Autodesk Fusion 360 part; units mm, degrees
(part 15 of 18)
  line L11676 (45.6204, -120.427) -> (45.1214, -120.123)
  line L11677 (160.483, -103.604) -> (159.889, -103.597)
  line L11678 (46.138, -120.698) -> (45.6204, -120.427)
  line L11679 (46.672, -120.935) -> (46.138, -120.698)
  line L11680 (87.7561, -119.027) -> (87.3513, -118.606)
  line L11681 (41.1245, -112.331) -> (41.1297, -112.925)
  line L11682 (41.1297, -112.925) -> (41.1742, -113.517)
  line L11683 (90.8336, -104.101) -> (91.3856, -103.909)
  line L11684 (59.1268, -112.55) -> (59.1251, -112.724)
  line L11685 (59.1079, -111.966) -> (59.1268, -112.55)
  line L11686 (54.0441, -120.684) -> (53.5109, -120.923)
  line L11687 (54.5607, -120.411) -> (54.0441, -120.684)
  line L11688 (55.0587, -120.105) -> (54.5607, -120.411)
  line L11689 (89.1214, -120.123) -> (88.643, -119.787)
  line L11690 (92.1233, -103.811) -> (91.5484, -103.959)
  line L11691 (55.2028, -105.092) -> (55.6734, -105.438)
  line L11692 (93.8893, -103.597) -> (93.2963, -103.629)
  line L11693 (54.7108, -104.776) -> (55.2028, -105.092)
  line L11694 (59.0274, -113.888) -> (58.9224, -114.462)
  line L11695 (59.0951, -113.307) -> (59.0274, -113.888)
  line L11696 (59.1251, -112.724) -> (59.0951, -113.307)
  line L11697 (90.672, -120.935) -> (90.138, -120.698)
  line L11698 (99.4411, -105.379) -> (98.954, -105.04)
  line L11699 (99.9045, -105.751) -> (99.4411, -105.379)
  line L11700 (46.8336, -104.101) -> (47.3856, -103.909)
  line L11701 (46.2951, -104.328) -> (46.8336, -104.101)
  line L11702 (56.5428, -106.218) -> (56.9379, -106.649)
  line L11703 (55.6734, -105.438) -> (56.1207, -105.814)
  line L11704 (92.35, -121.434) -> (91.7803, -121.304)
  line L11705 (56.1207, -105.814) -> (56.5428, -106.218)
  line L11706 (90.9847, -104.146) -> (90.4345, -104.369)
  line L11707 (92.7068, -103.7) -> (92.1233, -103.811)
  line L11708 (41.2769, -110.437) -> (41.4315, -109.874)
  line L11709 (41.1589, -111.01) -> (41.2769, -110.437)
  line L11710 (48.5208, -103.635) -> (49.0994, -103.553)
  line L11711 (47.9488, -103.754) -> (48.5208, -103.635)
  line L11712 (47.3856, -103.909) -> (47.9488, -103.754)
  line L11713 (93.2963, -103.629) -> (92.7068, -103.7)
  line L11714 (90.4345, -104.369) -> (89.9003, -104.629)
  line L11715 (94.0926, -121.6) -> (93.5085, -121.582)
  line L11716 (153.549, -106.42) -> (153.157, -106.866)
  line L11717 (41.8482, -108.783) -> (42.1085, -108.26)
  line L11718 (41.6223, -109.322) -> (41.8482, -108.783)
  line L11719 (153.97, -106.001) -> (153.549, -106.42)
  line L11720 (41.4315, -109.874) -> (41.6223, -109.322)
  line L11721 (95.8346, -121.428) -> (95.2581, -121.523)
  line L11722 (89.9003, -104.629) -> (89.3845, -104.923)
  line L11723 (88.417, -105.61) -> (87.9695, -106.001)
  line L11724 (58.5935, -115.317) -> (58.7582, -114.747)
  line L11725 (57.8006, -108.018) -> (57.4833, -107.517)
  line L11726 (58.084, -108.54) -> (57.8006, -108.018)
  line L11727 (58.3914, -115.876) -> (58.5935, -115.317)
  line L11728 (58.3321, -109.08) -> (58.084, -108.54)
  line L11729 (85.1742, -113.517) -> (85.2578, -114.105)
  line L11730 (98.4456, -104.733) -> (97.9179, -104.461)
  line L11731 (54.5813, -120.29) -> (55.0844, -119.974)
  line L11732 (58.9725, -113.579) -> (59.0211, -112.987)
  line L11733 (55.0844, -119.974) -> (55.5654, -119.626)
  line L11734 (58.8847, -114.167) -> (58.9725, -113.579)
  line L11735 (58.7582, -114.747) -> (58.8847, -114.167)
  line L11736 (85.0332, -112.331) -> (85.0347, -112.171)
  line L11737 (155.9, -104.629) -> (155.385, -104.923)
  line L11738 (85.2769, -110.437) -> (85.4315, -109.874)
  line L11739 (100.856, -118.401) -> (101.229, -117.939)
  line L11740 (87.2572, -118.354) -> (87.6569, -118.793)
  line L11741 (102.758, -114.747) -> (102.885, -114.167)
  line L11742 (92.9269, -121.527) -> (92.35, -121.434)
  line L11743 (103.032, -112.55) -> (103.012, -111.957)
  line L11744 (49.4521, -121.483) -> (50.0455, -121.505)
  line L11745 (56.453, -118.838) -> (56.8557, -118.401)
  line L11746 (56.0223, -119.247) -> (56.453, -118.838)
  line L11747 (48.8615, -121.422) -> (49.4521, -121.483)
  line L11748 (55.5654, -119.626) -> (56.0223, -119.247)
  line L11749 (85.0612, -113.339) -> (85.0291, -112.755)
  line L11750 (103.021, -112.987) -> (103.032, -112.55)
  line L11751 (102.972, -113.579) -> (103.021, -112.987)
  line L11752 (43.6569, -118.793) -> (44.0847, -119.205)
  line L11753 (51.2302, -121.43) -> (51.8162, -121.334)
  line L11754 (44.0847, -119.205) -> (44.539, -119.587)
  line L11755 (50.6391, -121.487) -> (51.2302, -121.43)
  line L11756 (50.0455, -121.505) -> (50.6391, -121.487)
  line L11757 (85.2379, -114.493) -> (85.1309, -113.919)
  line L11758 (101.133, -107.037) -> (100.753, -106.581)
  line L11759 (41.2578, -114.105) -> (41.3803, -114.686)
  line L11760 (41.1742, -113.517) -> (41.2578, -114.105)
  line L11761 (101.483, -107.517) -> (101.133, -107.037)
  line L11762 (45.0175, -119.939) -> (45.5183, -120.258)
  line L11763 (44.539, -119.587) -> (45.0175, -119.939)
  line L11764 (85.5618, -115.616) -> (85.3817, -115.06)
  line L11765 (177.268, -104.884) -> (177.772, -104.589)
  line L11766 (177.772, -104.589) -> (178.295, -104.328)
  line L11767 (41.7774, -116.159) -> (41.5618, -115.616)
  line L11768 (159.889, -103.597) -> (159.296, -103.629)
  line L11769 (42.0276, -116.687) -> (41.7774, -116.159)
  line L11770 (167.483, -107.517) -> (167.133, -107.037)
  line L11771 (41.7392, -115.817) -> (41.9741, -116.363)
  line L11772 (41.541, -115.258) -> (41.7392, -115.817)
  line L11773 (86.0276, -116.687) -> (85.7774, -116.159)
  line L11774 (178.295, -104.328) -> (178.834, -104.101)
  line L11775 (41.3803, -114.686) -> (41.541, -115.258)
  line L11776 (95.075, -103.651) -> (94.483, -103.604)
  line L11777 (47.2202, -121.137) -> (46.672, -120.935)
  line L11778 (47.7803, -121.304) -> (47.2202, -121.137)
  line L11779 (41.2379, -114.493) -> (41.1309, -113.919)
  line L11780 (85.3443, -110.566) -> (85.2321, -111.149)
  line L11781 (47.6987, -121.183) -> (48.2761, -121.322)
  line L11782 (57.1334, -107.037) -> (56.7525, -106.581)
  line L11783 (47.1318, -121.007) -> (47.6987, -121.183)
  line L11784 (54.0585, -120.571) -> (54.5813, -120.29)
  line L11785 (51.8162, -121.334) -> (52.3945, -121.2)
  line L11786 (59.0121, -111.957) -> (58.9531, -111.366)
  line L11787 (51.075, -103.651) -> (50.483, -103.604)
  line L11788 (57.8785, -116.946) -> (58.1527, -116.419)
  line L11789 (186.199, -104.494) -> (186.711, -104.776)
  line L11790 (53.5182, -120.817) -> (54.0585, -120.571)
  line L11791 (96.9634, -121.127) -> (96.4039, -121.296)
  line L11792 (102.659, -109.678) -> (102.827, -110.238)
  line L11793 (52.9627, -121.027) -> (53.5182, -120.817)
  line L11794 (161.663, -103.737) -> (161.075, -103.651)
  line L11795 (162.243, -103.861) -> (161.663, -103.737)
  line L11796 (152.795, -107.337) -> (152.466, -107.831)
  line L11797 (173.159, -111.01) -> (173.277, -110.437)
  line L11798 (152.466, -107.831) -> (152.17, -108.346)
  line L11799 (153.157, -106.866) -> (152.795, -107.337)
  line L11800 (151.232, -111.149) -> (151.159, -111.738)
  line L11801 (42.402, -107.754) -> (42.7274, -107.269)
  line L11802 (158.123, -103.811) -> (157.548, -103.959)
  line L11803 (49.5085, -121.582) -> (48.9269, -121.527)
  line L11804 (58.9224, -114.462) -> (58.7806, -115.029)
  line L11805 (45.3845, -104.923) -> (44.8893, -105.251)
  line L11806 (168.972, -113.579) -> (169.021, -112.987)
  line L11807 (58.7806, -115.029) -> (58.6024, -115.586)
  line L11808 (48.2761, -121.322) -> (48.8615, -121.422)
  line L11809 (100.823, -118.582) -> (100.42, -119.005)
  line L11810 (53.671, -104.244) -> (54.1995, -104.494)
  line L11811 (157.548, -103.959) -> (156.985, -104.146)
  line L11812 (175.469, -106.366) -> (175.882, -105.953)
  line L11813 (58.8266, -110.238) -> (58.9575, -110.808)
  line L11814 (167.57, -117.453) -> (167.879, -116.946)
  line L11815 (48.9269, -121.527) -> (48.35, -121.434)
  line L11816 (88.7829, -105.21) -> (89.2676, -104.884)
  line L11817 (168.084, -108.54) -> (167.801, -108.018)
  line L11818 (99.0587, -120.105) -> (98.5607, -120.411)
  line L11819 (57.5441, -117.663) -> (57.1986, -118.134)
  line L11820 (165.441, -105.379) -> (164.954, -105.04)
  line L11821 (43.2572, -118.354) -> (43.6569, -118.793)
  line L11822 (102.781, -115.029) -> (102.602, -115.586)
  line L11823 (98.5607, -120.411) -> (98.0441, -120.684)
  line L11824 (90.138, -120.698) -> (89.6204, -120.427)
  line L11825 (99.5654, -119.626) -> (100.022, -119.247)
  line L11826 (87.5489, -106.42) -> (87.157, -106.866)
  line L11827 (85.2578, -114.105) -> (85.3803, -114.686)
  line L11828 (58.8551, -110.78) -> (58.7185, -110.202)
  line L11829 (88.0847, -119.205) -> (88.539, -119.587)
  line L11830 (58.9575, -110.808) -> (59.0514, -111.384)
  line L11831 (154.889, -105.251) -> (154.417, -105.61)
  line L11832 (42.17, -108.346) -> (41.9088, -108.879)
  line L11833 (165.904, -105.751) -> (165.441, -105.379)
  line L11834 (90.0392, -120.543) -> (90.5778, -120.793)
  line L11835 (182.85, -103.533) -> (183.43, -103.602)
  line L11836 (58.1404, -116.659) -> (57.8585, -117.17)
  line L11837 (57.1986, -118.134) -> (56.8234, -118.582)
  line L11838 (50.8498, -103.533) -> (51.4301, -103.602)
  line L11839 (43.8816, -105.953) -> (44.3203, -105.567)
  line L11840 (102.456, -109.131) -> (102.659, -109.678)
  line L11841 (96.9627, -121.027) -> (97.5182, -120.817)
  line L11842 (86.3113, -117.198) -> (86.0276, -116.687)
  line L11843 (167.133, -107.037) -> (166.753, -106.581)
  line L11844 (168.953, -111.366) -> (168.855, -110.78)
  line L11845 (88.3203, -105.567) -> (88.7829, -105.21)
  line L11846 (179.949, -103.754) -> (180.521, -103.635)
  line L11847 (103.108, -111.966) -> (103.127, -112.55)
  line L11848 (46.0392, -120.543) -> (46.5778, -120.793)
  line L11849 (50.2663, -103.502) -> (50.8498, -103.533)
  line L11850 (168.885, -114.167) -> (168.972, -113.579)
  line L11851 (164.954, -105.04) -> (164.446, -104.733)
  line L11852 (101.199, -118.134) -> (100.823, -118.582)
  line L11853 (97.3734, -104.224) -> (96.8143, -104.024)
  line L11854 (102.602, -115.586) -> (102.389, -116.13)
  line L11855 (168.719, -110.202) -> (168.544, -109.635)
  line L11856 (43.0836, -106.806) -> (43.4688, -106.366)
  line L11857 (101.879, -116.946) -> (102.153, -116.419)
  line L11858 (151.683, -109.429) -> (151.495, -109.992)
  line L11859 (58.2178, -108.597) -> (58.4559, -109.131)
  line L11860 (85.4315, -109.874) -> (85.6222, -109.322)
  line L11861 (183.43, -103.602) -> (184.005, -103.708)
  line L11862 (85.6222, -109.322) -> (85.8482, -108.783)
  line L11863 (166.342, -106.152) -> (165.904, -105.751)
  line L11864 (92.5208, -103.635) -> (93.0994, -103.553)
  line L11865 (179.386, -103.909) -> (179.949, -103.754)
  line L11866 (91.2202, -121.137) -> (90.672, -120.935)
  line L11867 (94.6766, -121.58) -> (94.0926, -121.6)
  line L11868 (96.8143, -104.024) -> (96.2432, -103.861)
  line L11869 (102.855, -110.78) -> (102.719, -110.202)
  line L11870 (168.594, -115.317) -> (168.758, -114.747)
  line L11871 (102.544, -109.635) -> (102.332, -109.08)
  line L11872 (168.758, -114.747) -> (168.885, -114.167)
  line L11873 (102.719, -110.202) -> (102.544, -109.635)
  line L11874 (99.9903, -119.401) -> (99.5358, -119.768)
  line L11875 (156.434, -104.369) -> (155.9, -104.629)
  line L11876 (58.9531, -111.366) -> (58.8551, -110.78)
  line L11877 (184.571, -103.851) -> (185.128, -104.03)
  line L11878 (91.7803, -121.304) -> (91.2202, -121.137)
  line L11879 (44.7829, -105.21) -> (45.2676, -104.884)
  line L11880 (86.9746, -118.159) -> (86.6274, -117.689)
  line L11881 (41.0612, -113.339) -> (41.0291, -112.755)
  line L11882 (41.0291, -112.755) -> (41.0332, -112.331)
  line L11883 (166.453, -118.838) -> (166.856, -118.401)
  line L11884 (46.9847, -104.146) -> (46.4345, -104.369)
  line L11885 (42.9746, -118.159) -> (42.6274, -117.689)
  line L11886 (44.8893, -105.251) -> (44.417, -105.61)
  line L11887 (167.229, -117.939) -> (167.57, -117.453)
  line L11888 (88.643, -119.787) -> (88.1873, -119.421)
  line L11889 (86.5495, -117.401) -> (86.8876, -117.889)
  line L11890 (41.078, -111.588) -> (41.1589, -111.01)
  line L11891 (45.9003, -104.629) -> (45.3845, -104.923)
  line L11892 (162.814, -104.024) -> (162.243, -103.861)
  line L11893 (173.848, -108.783) -> (174.108, -108.26)
  line L11894 (57.9457, -108.08) -> (58.2178, -108.597)
  line L11895 (50.0926, -121.6) -> (49.5085, -121.582)
  line L11896 (42.466, -107.831) -> (42.17, -108.346)
  line L11897 (88.1873, -119.421) -> (87.7561, -119.027)
  line L11898 (93.682, -103.509) -> (94.2663, -103.502)
  line L11899 (94.2663, -103.502) -> (94.8498, -103.533)
  line L11900 (186.711, -104.776) -> (187.203, -105.092)
  line L11901 (100.121, -105.814) -> (100.543, -106.218)
  line L11902 (51.4301, -103.602) -> (52.0047, -103.708)
  line L11903 (100.42, -119.005) -> (99.9903, -119.401)
  line L11904 (59.0514, -111.384) -> (59.1079, -111.966)
  line L11905 (96.4039, -121.296) -> (95.8346, -121.428)
  line L11906 (156.985, -104.146) -> (156.434, -104.369)
  line L11907 (86.17, -108.346) -> (85.9088, -108.879)
  line L11908 (46.5778, -120.793) -> (47.1318, -121.007)
  line L11909 (89.2676, -104.884) -> (89.7724, -104.589)
  line L11910 (154.417, -105.61) -> (153.97, -106.001)
  line L11911 (48.35, -121.434) -> (47.7803, -121.304)
  line L11912 (85.2321, -111.149) -> (85.1587, -111.738)
  line L11913 (52.9634, -121.127) -> (52.4039, -121.296)
  line L11914 (98.0441, -120.684) -> (97.5109, -120.923)
  line L11915 (85.1297, -112.925) -> (85.1742, -113.517)
  line L11916 (44.3203, -105.567) -> (44.7829, -105.21)
  line L11917 (42.5495, -117.401) -> (42.8876, -117.889)
  line L11918 (87.4688, -106.366) -> (87.8816, -105.953)
  line L11919 (87.8816, -105.953) -> (88.3203, -105.567)
  line L11920 (165.565, -119.626) -> (166.022, -119.247)
  line L11921 (163.373, -104.224) -> (162.814, -104.024)
  line L11922 (173.277, -110.437) -> (173.432, -109.874)
  line L11923 (85.078, -111.588) -> (85.1589, -111.01)
  line L11924 (52.4039, -121.296) -> (51.8346, -121.428)
  line L11925 (86.7955, -107.337) -> (86.466, -107.831)
  line L11926 (57.8585, -117.17) -> (57.5441, -117.663)
  line L11927 (87.157, -106.866) -> (86.7955, -107.337)
  line L11928 (41.3817, -115.06) -> (41.2379, -114.493)
  line L11929 (146.389, -116.13) -> (146.14, -116.659)
  line L11930 (130.466, -107.831) -> (130.17, -108.346)
  line L11931 (123.133, -107.037) -> (122.753, -106.581)
  line L11932 (108.17, -108.346) -> (107.909, -108.879)
  line L11933 (157.949, -103.754) -> (158.521, -103.635)
  line L11934 (145.544, -117.663) -> (145.199, -118.134)
  line L11935 (143.203, -105.092) -> (143.673, -105.438)
  line L11936 (110.417, -105.61) -> (109.97, -106.001)
  line L11937 (138.046, -121.505) -> (138.639, -121.487)
  line L11938 (137.452, -121.483) -> (138.046, -121.505)
  line L11939 (107.159, -111.738) -> (107.124, -112.331)
  line L11940 (133.772, -104.589) -> (134.295, -104.328)
  line L11941 (164.561, -120.411) -> (164.044, -120.684)
  line L11942 (156.672, -120.935) -> (156.138, -120.698)
  line L11943 (155.018, -119.939) -> (155.518, -120.258)
  line L11944 (124.972, -113.579) -> (125.021, -112.987)
  line L11945 (166.938, -106.649) -> (167.304, -107.104)
  line L11946 (151.38, -114.686) -> (151.541, -115.258)
  line L11947 (159.099, -103.553) -> (159.682, -103.509)
  line L11948 (134.039, -120.543) -> (134.578, -120.793)
  line L11949 (109.97, -106.001) -> (109.549, -106.42)
  line L11950 (131.549, -106.42) -> (131.157, -106.866)
  line L11951 (121.565, -119.626) -> (122.022, -119.247)
  line L11952 (117.23, -121.43) -> (117.816, -121.334)
  line L11953 (112.985, -104.146) -> (112.434, -104.369)
  line L11954 (142.199, -104.494) -> (142.711, -104.776)
  line L11955 (146.659, -109.678) -> (146.827, -110.238)
  line L11956 (159.509, -121.582) -> (158.927, -121.527)
  line L11957 (140.963, -121.127) -> (140.404, -121.296)
  line L11958 (138.677, -121.58) -> (138.093, -121.6)
  line L11959 (151.258, -114.105) -> (151.38, -114.686)
  line L11960 (142.561, -120.411) -> (142.044, -120.684)
  line L11961 (139.075, -103.651) -> (138.483, -103.604)
  line L11962 (141.511, -120.923) -> (140.963, -121.127)
  line L11963 (125.125, -112.724) -> (125.095, -113.307)
  line L11964 (123.483, -107.517) -> (123.133, -107.037)
  line L11965 (163.511, -120.923) -> (162.963, -121.127)
  line L11966 (129.683, -109.429) -> (129.495, -109.992)
  line L11967 (130.245, -116.891) -> (130.55, -117.401)
  line L11968 (145.858, -117.17) -> (145.544, -117.663)
  line L11969 (107.124, -112.331) -> (107.13, -112.925)
  line L11970 (146.391, -115.876) -> (146.594, -115.317)
  line L11971 (141.671, -104.244) -> (142.199, -104.494)
  line L11972 (165.673, -105.438) -> (166.121, -105.814)
  line L11973 (161.258, -121.523) -> (160.677, -121.58)
  line L11974 (132.32, -105.567) -> (132.783, -105.21)
  line L11975 (144.856, -118.401) -> (145.229, -117.939)
  line L11976 (129.739, -115.817) -> (129.974, -116.363)
  line L11977 (146.218, -108.597) -> (146.456, -109.131)
  line L11978 (145.879, -116.946) -> (146.153, -116.419)
  line L11979 (146.456, -109.131) -> (146.659, -109.678)
  line L11980 (108.466, -107.831) -> (108.17, -108.346)
  line L11981 (142.711, -104.776) -> (143.203, -105.092)
  line L11982 (152.727, -107.269) -> (153.084, -106.806)
  line L11983 (115.296, -103.629) -> (114.707, -103.7)
  line L11984 (146.957, -110.808) -> (147.051, -111.384)
  line L11985 (152.108, -108.26) -> (152.402, -107.754)
  line L11986 (142.581, -120.29) -> (143.084, -119.974)
  line L11987 (117.663, -103.737) -> (117.075, -103.651)
  line L11988 (146.602, -115.586) -> (146.389, -116.13)
  line L11989 (135.78, -121.304) -> (135.22, -121.137)
  line L11990 (157.132, -121.007) -> (157.699, -121.183)
  line L11991 (151.061, -113.339) -> (151.029, -112.755)
  line L11992 (136.35, -121.434) -> (135.78, -121.304)
  line L11993 (143.084, -119.974) -> (143.565, -119.626)
  line L11994 (151.277, -110.437) -> (151.432, -109.874)
  line L11995 (129.777, -116.159) -> (129.562, -115.616)
  line L11996 (147.108, -111.966) -> (147.127, -112.55)
  line L11997 (139.816, -121.334) -> (140.395, -121.2)
  line L11998 (158.521, -103.635) -> (159.099, -103.553)
  line L11999 (153.257, -118.354) -> (153.657, -118.793)
  line L12000 (146.084, -108.54) -> (145.801, -108.018)
  line L12001 (143.565, -119.626) -> (144.022, -119.247)
  line L12002 (109.157, -106.866) -> (108.795, -107.337)
  line L12003 (146.827, -110.238) -> (146.957, -110.808)
  line L12004 (141.128, -104.03) -> (141.671, -104.244)
  line L12005 (135.22, -121.137) -> (134.672, -120.935)
  line L12006 (169.027, -113.888) -> (168.922, -114.462)
  line L12007 (168.957, -110.808) -> (169.051, -111.384)
  line L12008 (124.544, -109.635) -> (124.332, -109.08)
  line L12009 (124.758, -114.747) -> (124.885, -114.167)
  line L12010 (145.483, -107.517) -> (145.133, -107.037)
  line L12011 (129.232, -111.149) -> (129.159, -111.738)
  line L12012 (129.541, -115.258) -> (129.739, -115.817)
  line L12013 (136.861, -121.422) -> (137.452, -121.483)
  line L12014 (153.084, -106.806) -> (153.469, -106.366)
  line L12015 (135.548, -103.959) -> (134.985, -104.146)
  line L12016 (129.432, -109.874) -> (129.622, -109.322)
  line L12017 (119.511, -120.923) -> (118.963, -121.127)
  line L12018 (159.452, -121.483) -> (160.046, -121.505)
  line L12019 (141.518, -120.817) -> (142.059, -120.571)
  line L12020 (144.022, -119.247) -> (144.453, -118.838)
  line L12021 (152.975, -118.159) -> (152.627, -117.689)
  line L12022 (139.23, -121.43) -> (139.816, -121.334)
  line L12023 (112.138, -120.698) -> (111.62, -120.427)
  line L12024 (168.922, -114.462) -> (168.781, -115.029)
  line L12025 (154.187, -119.421) -> (153.756, -119.027)
  line L12026 (146.885, -114.167) -> (146.972, -113.579)
  line L12027 (140.571, -103.851) -> (141.128, -104.03)
  line L12028 (142.059, -120.571) -> (142.581, -120.29)
  line L12029 (159.682, -103.509) -> (160.266, -103.502)
  line L12030 (151.029, -112.755) -> (151.033, -112.331)
  line L12031 (165.536, -119.768) -> (165.059, -120.105)
  line L12032 (164.044, -120.684) -> (163.511, -120.923)
  line L12033 (140.814, -104.024) -> (140.243, -103.861)
  line L12034 (136.276, -121.322) -> (136.861, -121.422)
  line L12035 (121.084, -119.974) -> (121.565, -119.626)
  line L12036 (122.543, -106.218) -> (122.938, -106.649)
  line L12037 (108.028, -116.687) -> (107.777, -116.159)
  line L12038 (147.032, -112.55) -> (147.012, -111.957)
  line L12039 (118.404, -121.296) -> (117.835, -121.428)
  line L12040 (131.157, -106.866) -> (130.795, -107.337)
  line L12041 (168.659, -109.678) -> (168.827, -110.238)
  line L12042 (107.344, -110.566) -> (107.232, -111.149)
  line L12043 (160.093, -121.6) -> (159.509, -121.582)
  line L12044 (153.756, -119.027) -> (153.351, -118.606)
  line L12045 (108.795, -107.337) -> (108.466, -107.831)
  line L12046 (116.639, -121.487) -> (117.23, -121.43)
  line L12047 (124.594, -115.317) -> (124.758, -114.747)
  line L12048 (162.571, -103.851) -> (163.128, -104.03)
  line L12049 (130.17, -108.346) -> (129.909, -108.879)
  line L12050 (119.918, -104.461) -> (119.373, -104.224)
  line L12051 (140.395, -121.2) -> (140.963, -121.027)
  line L12052 (144.453, -118.838) -> (144.856, -118.401)
  line L12053 (145.133, -107.037) -> (144.753, -106.581)
  line L12054 (112.434, -104.369) -> (111.9, -104.629)
  line L12055 (129.344, -110.566) -> (129.232, -111.149)
  line L12056 (121.904, -105.751) -> (121.441, -105.379)
  line L12057 (131.084, -106.806) -> (131.469, -106.366)
  line L12058 (131.469, -106.366) -> (131.882, -105.953)
  line L12059 (166.42, -119.005) -> (165.99, -119.401)
  line L12060 (163.518, -120.817) -> (164.059, -120.571)
  line L12061 (131.257, -118.354) -> (131.657, -118.793)
  line L12062 (125.012, -111.957) -> (124.953, -111.366)
  line L12063 (129.277, -110.437) -> (129.432, -109.874)
  line L12064 (130.888, -117.889) -> (131.257, -118.354)
  line L12065 (129.078, -111.588) -> (129.159, -111.01)
  line L12066 (146.781, -115.029) -> (146.602, -115.586)
  line L12067 (134.985, -104.146) -> (134.434, -104.369)
  line L12068 (132.889, -105.251) -> (132.417, -105.61)
  line L12069 (132.539, -119.587) -> (133.018, -119.939)
  line L12070 (164.199, -104.494) -> (164.711, -104.776)
  line L12071 (137.889, -103.597) -> (137.296, -103.629)
  line L12072 (107.382, -115.06) -> (107.238, -114.493)
  line L12073 (116.046, -121.505) -> (116.639, -121.487)
  line L12074 (131.756, -119.027) -> (131.351, -118.606)
  line L12075 (124.719, -110.202) -> (124.544, -109.635)
  line L12076 (133.9, -104.629) -> (133.385, -104.923)
  line L12077 (114.35, -121.434) -> (113.78, -121.304)
  line L12078 (140.243, -103.861) -> (139.663, -103.737)
  line L12079 (107.683, -109.429) -> (107.495, -109.992)
  line L12080 (157.386, -103.909) -> (157.949, -103.754)
  line L12081 (109.549, -106.42) -> (109.157, -106.866)
  line L12082 (151.432, -109.874) -> (151.622, -109.322)
  line L12083 (162.395, -121.2) -> (162.963, -121.027)
  line L12084 (118.243, -103.861) -> (117.663, -103.737)
  line L12085 (110.085, -119.205) -> (110.539, -119.587)
  line L12086 (124.957, -110.808) -> (125.051, -111.384)
  line L12087 (121.059, -120.105) -> (120.561, -120.411)
  line L12088 (131.351, -118.606) -> (130.975, -118.159)
  line L12089 (154.32, -105.567) -> (154.783, -105.21)
  line L12090 (168.14, -116.659) -> (167.858, -117.17)
  line L12091 (168.456, -109.131) -> (168.659, -109.678)
  line L12092 (113.22, -121.137) -> (112.672, -120.935)
  line L12093 (167.641, -107.581) -> (167.946, -108.08)
  line L12094 (107.541, -115.258) -> (107.739, -115.817)
  line L12095 (124.602, -115.586) -> (124.389, -116.13)
  line L12096 (111.018, -119.939) -> (111.518, -120.258)
  line L12097 (109.657, -118.793) -> (110.085, -119.205)
  line L12098 (111.385, -104.923) -> (110.889, -105.251)
  line L12099 (109.351, -118.606) -> (108.975, -118.159)
  line L12100 (136.707, -103.7) -> (136.123, -103.811)
  line L12101 (110.539, -119.587) -> (111.018, -119.939)
  line L12102 (129.13, -112.925) -> (129.174, -113.517)
  line L12103 (145.304, -107.104) -> (145.641, -107.581)
  line L12104 (110.643, -119.787) -> (110.187, -119.421)
  line L12105 (107.739, -115.817) -> (107.974, -116.363)
  line L12106 (134.295, -104.328) -> (134.834, -104.101)
  line L12107 (107.495, -109.992) -> (107.344, -110.566)
  line L12108 (146.594, -115.317) -> (146.758, -114.747)
  line L12109 (145.641, -107.581) -> (145.946, -108.08)
  line L12110 (122.938, -106.649) -> (123.304, -107.104)
  line L12111 (147.051, -111.384) -> (147.108, -111.966)
  line L12112 (162.963, -121.027) -> (163.518, -120.817)
  line L12113 (163.128, -104.03) -> (163.671, -104.244)
  line L12114 (109.756, -119.027) -> (109.351, -118.606)
  line L12115 (168.389, -116.13) -> (168.14, -116.659)
  line L12116 (158.861, -121.422) -> (159.452, -121.483)
  line L12117 (135.132, -121.007) -> (135.699, -121.183)
  line L12118 (107.029, -112.755) -> (107.033, -112.331)
  line L12119 (117.258, -121.523) -> (116.677, -121.58)
  line L12120 (151.848, -108.783) -> (152.108, -108.26)
  line L12121 (125.032, -112.55) -> (125.012, -111.957)
  line L12122 (156.138, -120.698) -> (155.62, -120.427)
  line L12123 (119.518, -120.817) -> (120.059, -120.571)
  line L12124 (118.963, -121.127) -> (118.404, -121.296)
  line L12125 (146.14, -116.659) -> (145.858, -117.17)
  line L12126 (151.035, -112.171) -> (151.078, -111.588)
  line L12127 (146.153, -116.419) -> (146.391, -115.876)
  line L12128 (133.518, -120.258) -> (134.039, -120.543)
  line L12129 (129.909, -108.879) -> (129.683, -109.429)
  line L12130 (155.62, -120.427) -> (155.121, -120.123)
  line L12131 (133.268, -104.884) -> (133.772, -104.589)
  line L12132 (122.121, -105.814) -> (122.543, -106.218)
  line L12133 (151.159, -111.01) -> (151.277, -110.437)
  line L12134 (135.949, -103.754) -> (136.521, -103.635)
  line L12135 (144.823, -118.582) -> (144.42, -119.005)
  line L12136 (130.55, -117.401) -> (130.888, -117.889)
  line L12137 (146.332, -109.08) -> (146.084, -108.54)
  line L12138 (146.953, -111.366) -> (146.855, -110.78)
  line L12139 (138.639, -121.487) -> (139.23, -121.43)
  line L12140 (151.777, -116.159) -> (151.562, -115.616)
  line L12141 (116.483, -103.604) -> (115.889, -103.597)
  line L12142 (168.602, -115.586) -> (168.389, -116.13)
  line L12143 (107.562, -115.616) -> (107.382, -115.06)
  line L12144 (120.581, -120.29) -> (121.084, -119.974)
  line L12145 (147.125, -112.724) -> (147.095, -113.307)
  line L12146 (132.783, -105.21) -> (133.268, -104.884)
  line L12147 (124.922, -114.462) -> (124.781, -115.029)
  line L12148 (169.108, -111.966) -> (169.127, -112.55)
  line L12149 (142.044, -120.684) -> (141.511, -120.923)
  line L12150 (129.848, -108.783) -> (130.108, -108.26)
  line L12151 (158.276, -121.322) -> (158.861, -121.422)
  line L12152 (152.402, -107.754) -> (152.727, -107.269)
  line L12153 (166.823, -118.582) -> (166.42, -119.005)
  line L12154 (108.975, -118.159) -> (108.627, -117.689)
  line L12155 (140.404, -121.296) -> (139.835, -121.428)
  line L12156 (156.834, -104.101) -> (157.386, -103.909)
  line L12157 (107.174, -113.517) -> (107.258, -114.105)
  line L12158 (163.671, -104.244) -> (164.199, -104.494)
  line L12159 (165.059, -120.105) -> (164.561, -120.411)
  line L12160 (133.385, -104.923) -> (132.889, -105.251)
  line L12161 (146.719, -110.202) -> (146.544, -109.635)
  line L12162 (146.855, -110.78) -> (146.719, -110.202)
  line L12163 (123.879, -116.946) -> (124.153, -116.419)
  line L12164 (146.972, -113.579) -> (147.021, -112.987)
  line L12165 (129.061, -113.339) -> (129.029, -112.755)
  line L12166 (124.332, -109.08) -> (124.084, -108.54)
  line L12167 (165.99, -119.401) -> (165.536, -119.768)
  line L12168 (134.578, -120.793) -> (135.132, -121.007)
  line L12169 (107.258, -114.105) -> (107.38, -114.686)
  line L12170 (147.021, -112.987) -> (147.032, -112.55)
  line L12171 (167.946, -108.08) -> (168.218, -108.597)
  line L12172 (151.131, -113.919) -> (151.061, -113.339)
  line L12173 (139.43, -103.602) -> (140.005, -103.708)
  line L12174 (121.441, -105.379) -> (120.954, -105.04)
  line L12175 (147.012, -111.957) -> (146.953, -111.366)
  line L12176 (161.23, -121.43) -> (161.816, -121.334)
  line L12177 (153.882, -105.953) -> (154.32, -105.567)
  line L12178 (124.781, -115.029) -> (124.602, -115.586)
  line L12179 (123.858, -117.17) -> (123.544, -117.663)
  line L12180 (137.509, -121.582) -> (136.927, -121.527)
  line L12181 (132.417, -105.61) -> (131.97, -106.001)
  line L12182 (145.801, -108.018) -> (145.483, -107.517)
  line L12183 (156.578, -120.793) -> (157.132, -121.007)
  line L12184 (122.453, -118.838) -> (122.856, -118.401)
  line L12185 (115.509, -121.582) -> (114.927, -121.527)
  line L12186 (138.266, -103.502) -> (138.85, -103.533)
  line L12187 (117.075, -103.651) -> (116.483, -103.604)
  line L12188 (154.085, -119.205) -> (154.539, -119.587)
  line L12189 (140.005, -103.708) -> (140.571, -103.851)
  line L12190 (124.855, -110.78) -> (124.719, -110.202)
  line L12191 (120.044, -120.684) -> (119.511, -120.923)
  line L12192 (169.051, -111.384) -> (169.108, -111.966)
  line L12193 (146.758, -114.747) -> (146.885, -114.167)
  line L12194 (129.974, -116.363) -> (130.245, -116.891)
  line L12195 (124.885, -114.167) -> (124.972, -113.579)
  line L12196 (123.641, -107.581) -> (123.946, -108.08)
  line L12197 (160.639, -121.487) -> (161.23, -121.43)
  line L12198 (118.814, -104.024) -> (118.243, -103.861)
  line L12199 (145.57, -117.453) -> (145.879, -116.946)
  line L12200 (116.093, -121.6) -> (115.509, -121.582)
  line L12201 (142.446, -104.733) -> (141.918, -104.461)
  line L12202 (168.218, -108.597) -> (168.456, -109.131)
  line L12203 (130.975, -118.159) -> (130.627, -117.689)
  line L12204 (169.125, -112.724) -> (169.095, -113.307)
  line L12205 (123.946, -108.08) -> (124.218, -108.597)
  line L12206 (155.772, -104.589) -> (156.295, -104.328)
  line L12207 (152.311, -117.198) -> (152.028, -116.687)
  line L12208 (125.027, -113.888) -> (124.922, -114.462)
  line L12209 (161.835, -121.428) -> (161.258, -121.523)
  line L12210 (116.677, -121.58) -> (116.093, -121.6)
  line L12211 (138.85, -103.533) -> (139.43, -103.602)
  line L12212 (157.699, -121.183) -> (158.276, -121.322)
  line L12213 (107.909, -108.879) -> (107.683, -109.429)
  line L12214 (144.543, -106.218) -> (144.938, -106.649)
  line L12215 (129.033, -112.331) -> (129.035, -112.171)
  line L12216 (123.57, -117.453) -> (123.879, -116.946)
  line L12217 (135.386, -103.909) -> (135.949, -103.754)
  line L12218 (108.627, -117.689) -> (108.311, -117.198)
  line L12219 (122.823, -118.582) -> (122.42, -119.005)
  line L12220 (147.027, -113.888) -> (146.922, -114.462)
  line L12221 (118.963, -121.027) -> (119.518, -120.817)
  line L12222 (169.127, -112.55) -> (169.125, -112.724)
  line L12223 (110.889, -105.251) -> (110.417, -105.61)
  line L12224 (129.131, -113.919) -> (129.061, -113.339)
  line L12225 (156.295, -104.328) -> (156.834, -104.101)
  line L12226 (134.672, -120.935) -> (134.138, -120.698)
  line L12227 (107.033, -112.331) -> (107.035, -112.171)
  line L12228 (129.495, -109.992) -> (129.344, -110.566)
  line L12229 (144.342, -106.152) -> (143.904, -105.751)
  line L12230 (166.543, -106.218) -> (166.938, -106.649)
  line L12231 (154.783, -105.21) -> (155.268, -104.884)
  line L12232 (129.382, -115.06) -> (129.238, -114.493)
  line L12233 (139.663, -103.737) -> (139.075, -103.651)
  line L12234 (162.404, -121.296) -> (161.835, -121.428)
  line L12235 (155.518, -120.258) -> (156.039, -120.543)
  line L12236 (131.97, -106.001) -> (131.549, -106.42)
  line L12237 (107.035, -112.171) -> (107.078, -111.588)
  line L12238 (137.296, -103.629) -> (136.707, -103.7)
  line L12239 (153.657, -118.793) -> (154.085, -119.205)
  line L12240 (161.43, -103.602) -> (162.005, -103.708)
  line L12241 (142.954, -105.04) -> (142.446, -104.733)
  line L12242 (129.124, -112.331) -> (129.13, -112.925)
  line L12243 (167.544, -117.663) -> (167.199, -118.134)
  line L12244 (133.121, -120.123) -> (132.643, -119.787)
  line L12245 (124.14, -116.659) -> (123.858, -117.17)
  line L12246 (123.304, -107.104) -> (123.641, -107.581)
  line L12247 (129.029, -112.755) -> (129.033, -112.331)
  line L12248 (125.021, -112.987) -> (125.032, -112.55)
  line L12249 (119.373, -104.224) -> (118.814, -104.024)
  line L12250 (166.121, -105.814) -> (166.543, -106.218)
  line L12251 (112.578, -120.793) -> (113.132, -121.007)
  line L12252 (112.039, -120.543) -> (112.578, -120.793)
  line L12253 (146.922, -114.462) -> (146.781, -115.029)
  line L12254 (120.059, -120.571) -> (120.581, -120.29)
  line L12255 (129.174, -113.517) -> (129.258, -114.105)
  line L12256 (162.963, -121.127) -> (162.404, -121.296)
  line L12257 (114.707, -103.7) -> (114.123, -103.811)
  line L12258 (168.781, -115.029) -> (168.602, -115.586)
  line L12259 (155.268, -104.884) -> (155.772, -104.589)
  line L12260 (107.232, -111.149) -> (107.159, -111.738)
  line L12261 (145.199, -118.134) -> (144.823, -118.582)
  line L12262 (151.974, -116.363) -> (152.245, -116.891)
  line L12263 (143.904, -105.751) -> (143.441, -105.379)
  line L12264 (120.954, -105.04) -> (120.446, -104.733)
  line L12265 (113.699, -121.183) -> (114.276, -121.322)
  line L12266 (124.659, -109.678) -> (124.827, -110.238)
  line L12267 (113.132, -121.007) -> (113.699, -121.183)
  line L12268 (134.834, -104.101) -> (135.386, -103.909)
  line L12269 (117.835, -121.428) -> (117.258, -121.523)
  line L12270 (124.953, -111.366) -> (124.855, -110.78)
  line L12271 (124.218, -108.597) -> (124.456, -109.131)
  line L12272 (151.033, -112.331) -> (151.035, -112.171)
  line L12273 (141.918, -104.461) -> (141.373, -104.224)
  line L12274 (165.084, -119.974) -> (165.565, -119.626)
  line L12275 (124.456, -109.131) -> (124.659, -109.678)
  line L12276 (114.276, -121.322) -> (114.861, -121.422)
  line L12277 (146.544, -109.635) -> (146.332, -109.08)
  line L12278 (125.095, -113.307) -> (125.027, -113.888)
  line L12279 (130.108, -108.26) -> (130.402, -107.754)
  line L12280 (165.203, -105.092) -> (165.673, -105.438)
  line L12281 (137.682, -103.509) -> (138.266, -103.502)
  line L12282 (144.753, -106.581) -> (144.342, -106.152)
  line L12283 (108.245, -116.891) -> (108.55, -117.401)
  line L12284 (139.258, -121.523) -> (138.677, -121.58)
  line L12285 (160.677, -121.58) -> (160.093, -121.6)
  line L12286 (139.835, -121.428) -> (139.258, -121.523)
  line L12287 (132.643, -119.787) -> (132.187, -119.421)
  line L12288 (157.78, -121.304) -> (157.22, -121.137)
  line L12289 (160.85, -103.533) -> (161.43, -103.602)
  line L12290 (113.548, -103.959) -> (112.985, -104.146)
  line L12291 (151.078, -111.588) -> (151.159, -111.01)
  line L12292 (124.153, -116.419) -> (124.391, -115.876)
  line L12293 (162.005, -103.708) -> (162.571, -103.851)
  line L12294 (161.816, -121.334) -> (162.395, -121.2)
  line L12295 (130.311, -117.198) -> (130.028, -116.687)
  line L12296 (164.711, -104.776) -> (165.203, -105.092)
  line L12297 (155.121, -120.123) -> (154.643, -119.787)
  line L12298 (122.856, -118.401) -> (123.229, -117.939)
  line L12299 (123.801, -108.018) -> (123.483, -107.517)
  line L12300 (124.391, -115.876) -> (124.594, -115.317)
  line L12301 (131.657, -118.793) -> (132.085, -119.205)
  line L12302 (135.699, -121.183) -> (136.276, -121.322)
  line L12303 (145.229, -117.939) -> (145.57, -117.453)
  line L12304 (110.187, -119.421) -> (109.756, -119.027)
  line L12305 (114.123, -103.811) -> (113.548, -103.959)
  line L12306 (164.059, -120.571) -> (164.581, -120.29)
  line L12307 (125.127, -112.55) -> (125.125, -112.724)
  line L12308 (151.238, -114.493) -> (151.131, -113.919)
  line L12309 (167.199, -118.134) -> (166.823, -118.582)
  line L12310 (129.38, -114.686) -> (129.541, -115.258)
  line L12311 (124.084, -108.54) -> (123.801, -108.018)
  line L12312 (134.138, -120.698) -> (133.62, -120.427)
  line L12313 (167.858, -117.17) -> (167.544, -117.663)
  line L12314 (133.62, -120.427) -> (133.121, -120.123)
  line L12315 (145.946, -108.08) -> (146.218, -108.597)
  line L12316 (125.051, -111.384) -> (125.108, -111.966)
  line L12317 (121.536, -119.768) -> (121.059, -120.105)
  line L12318 (124.827, -110.238) -> (124.957, -110.808)
  line L12319 (122.42, -119.005) -> (121.99, -119.401)
  line L12320 (122.342, -106.152) -> (121.904, -105.751)
  line L12321 (111.62, -120.427) -> (111.121, -120.123)
  line L12322 (129.622, -109.322) -> (129.848, -108.783)
  line L12323 (144.121, -105.814) -> (144.543, -106.218)
  line L12324 (134.434, -104.369) -> (133.9, -104.629)
  line L12325 (137.099, -103.553) -> (137.682, -103.509)
  line L12326 (138.093, -121.6) -> (137.509, -121.582)
  line L12327 (120.561, -120.411) -> (120.044, -120.684)
  line L12328 (140.963, -121.027) -> (141.518, -120.817)
  line L12329 (158.927, -121.527) -> (158.35, -121.434)
  line L12330 (141.373, -104.224) -> (140.814, -104.024)
  line L12331 (154.643, -119.787) -> (154.187, -119.421)
  line L12332 (152.028, -116.687) -> (151.777, -116.159)
  line L12333 (153.469, -106.366) -> (153.882, -105.953)
  line L12334 (143.673, -105.438) -> (144.121, -105.814)
  line L12335 (151.562, -115.616) -> (151.382, -115.06)
  line L12336 (107.061, -113.339) -> (107.029, -112.755)
  line L12337 (123.229, -117.939) -> (123.57, -117.453)
  line L12338 (123.199, -118.134) -> (122.823, -118.582)
  line L12339 (152.627, -117.689) -> (152.311, -117.198)
  line L12340 (108.888, -117.889) -> (109.257, -118.354)
  line L12341 (122.753, -106.581) -> (122.342, -106.152)
  line L12342 (136.521, -103.635) -> (137.099, -103.553)
  line L12343 (147.095, -113.307) -> (147.027, -113.888)
  line L12344 (107.131, -113.919) -> (107.061, -113.339)
  line L12345 (132.187, -119.421) -> (131.756, -119.027)
  line L12346 (115.889, -103.597) -> (115.296, -103.629)
  line L12347 (129.562, -115.616) -> (129.382, -115.06)
  line L12348 (151.739, -115.817) -> (151.974, -116.363)
  line L12349 (117.816, -121.334) -> (118.395, -121.2)
  line L12350 (111.518, -120.258) -> (112.039, -120.543)
  line L12351 (118.395, -121.2) -> (118.963, -121.027)
  line L12352 (123.544, -117.663) -> (123.199, -118.134)
  line L12353 (130.028, -116.687) -> (129.777, -116.159)
  line L12354 (112.672, -120.935) -> (112.138, -120.698)
  line L12355 (107.974, -116.363) -> (108.245, -116.891)
  line L12356 (151.541, -115.258) -> (151.739, -115.817)
  line L12357 (147.127, -112.55) -> (147.125, -112.724)
  line L12358 (168.827, -110.238) -> (168.957, -110.808)
  line L12359 (143.441, -105.379) -> (142.954, -105.04)
  line L12360 (125.108, -111.966) -> (125.127, -112.55)
  line L12361 (151.622, -109.322) -> (151.848, -108.783)
  line L12362 (107.238, -114.493) -> (107.131, -113.919)
  line L12363 (164.581, -120.29) -> (165.084, -119.974)
  line L12364 (129.035, -112.171) -> (129.078, -111.588)
  line L12365 (143.99, -119.401) -> (143.536, -119.768)
  line L12366 (111.9, -104.629) -> (111.385, -104.923)
  line L12367 (113.78, -121.304) -> (113.22, -121.137)
  line L12368 (156.039, -120.543) -> (156.578, -120.793)
  line L12369 (152.888, -117.889) -> (153.257, -118.354)
  line L12370 (152.245, -116.891) -> (152.55, -117.401)
  line L12371 (111.121, -120.123) -> (110.643, -119.787)
  line L12372 (114.927, -121.527) -> (114.35, -121.434)
  line L12373 (153.351, -118.606) -> (152.975, -118.159)
  line L12374 (120.446, -104.733) -> (119.918, -104.461)
  line L12375 (121.673, -105.438) -> (122.121, -105.814)
  line L12376 (151.174, -113.517) -> (151.258, -114.105)
  line L12377 (129.238, -114.493) -> (129.131, -113.919)
  line L12378 (133.018, -119.939) -> (133.518, -120.258)
  line L12379 (129.159, -111.01) -> (129.277, -110.437)
  line L12380 (143.536, -119.768) -> (143.059, -120.105)
  line L12381 (143.059, -120.105) -> (142.561, -120.411)
  line L12382 (124.389, -116.13) -> (124.14, -116.659)
  line L12383 (122.022, -119.247) -> (122.453, -118.838)
  line L12384 (144.938, -106.649) -> (145.304, -107.104)
  line L12385 (157.22, -121.137) -> (156.672, -120.935)
  line L12386 (144.42, -119.005) -> (143.99, -119.401)
  line L12387 (130.402, -107.754) -> (130.727, -107.269)
  line L12388 (130.727, -107.269) -> (131.084, -106.806)
  line L12389 (151.382, -115.06) -> (151.238, -114.493)
  line L12390 (121.203, -105.092) -> (121.673, -105.438)
  line L12391 (130.795, -107.337) -> (130.466, -107.831)
  line L12392 (121.99, -119.401) -> (121.536, -119.768)
  line L12393 (154.539, -119.587) -> (155.018, -119.939)
  line L12394 (167.304, -107.104) -> (167.641, -107.581)
  line L12395 (108.55, -117.401) -> (108.888, -117.889)
  line L12396 (115.452, -121.483) -> (116.046, -121.505)
  line L12397 (158.35, -121.434) -> (157.78, -121.304)
  line L12398 (130.627, -117.689) -> (130.311, -117.198)
  line L12399 (129.258, -114.105) -> (129.38, -114.686)
  line L12400 (160.266, -103.502) -> (160.85, -103.533)
  line L12401 (136.927, -121.527) -> (136.35, -121.434)
  line L12402 (108.311, -117.198) -> (108.028, -116.687)
  line L12403 (107.777, -116.159) -> (107.562, -115.616)
  line L12404 (136.123, -103.811) -> (135.548, -103.959)
  line L12405 (131.882, -105.953) -> (132.32, -105.567)
  line L12406 (152.55, -117.401) -> (152.888, -117.889)
  line L12407 (114.861, -121.422) -> (115.452, -121.483)
  line L12408 (132.085, -119.205) -> (132.539, -119.587)
  line L12409 (138.483, -103.604) -> (137.889, -103.597)
  line L12410 (107.13, -112.925) -> (107.174, -113.517)
  line L12411 (169.095, -113.307) -> (169.027, -113.888)
  line L12412 (107.38, -114.686) -> (107.541, -115.258)
  line L12413 (109.257, -118.354) -> (109.657, -118.793)
  line L12414 (160.046, -121.505) -> (160.639, -121.487)
  line L12415 (129.159, -111.738) -> (129.124, -112.331)
sketch "8x8-Edge_Cuts" plane through (0, 0, 0) normal (0, 0, 1) x (1, 0, 0)
  line L0 (193, -29.45) -> (193.035, -29.4646)
  line L1 (16.9646, -29.4646) -> (17, -29.45)
  line L2 (16.9646, -219.135) -> (16.95, -219.1)
  line L3 (16.95, -219.1) -> (16.95, -29.5)
  line L4 (193.035, -29.4646) -> (193.05, -29.5)
  line L5 (16.95, -29.5) -> (16.9646, -29.4646)
  line L6 (17, -29.45) -> (193, -29.45)
  line L7 (193, -219.15) -> (17, -219.15)
  line L8 (193.035, -219.135) -> (193, -219.15)
  line L9 (193.05, -219.1) -> (193.035, -219.135)
  line L10 (193.05, -29.5) -> (193.05, -219.1)
  line L11 (17.05, -29.55) -> (17.05, -219.05)
  line L12 (192.95, -29.55) -> (17.05, -29.55)
  line L13 (192.95, -219.05) -> (192.95, -29.55)
  line L14 (17.05, -219.05) -> (192.95, -219.05)
  line L15 (17, -219.15) -> (16.9646, -219.135)